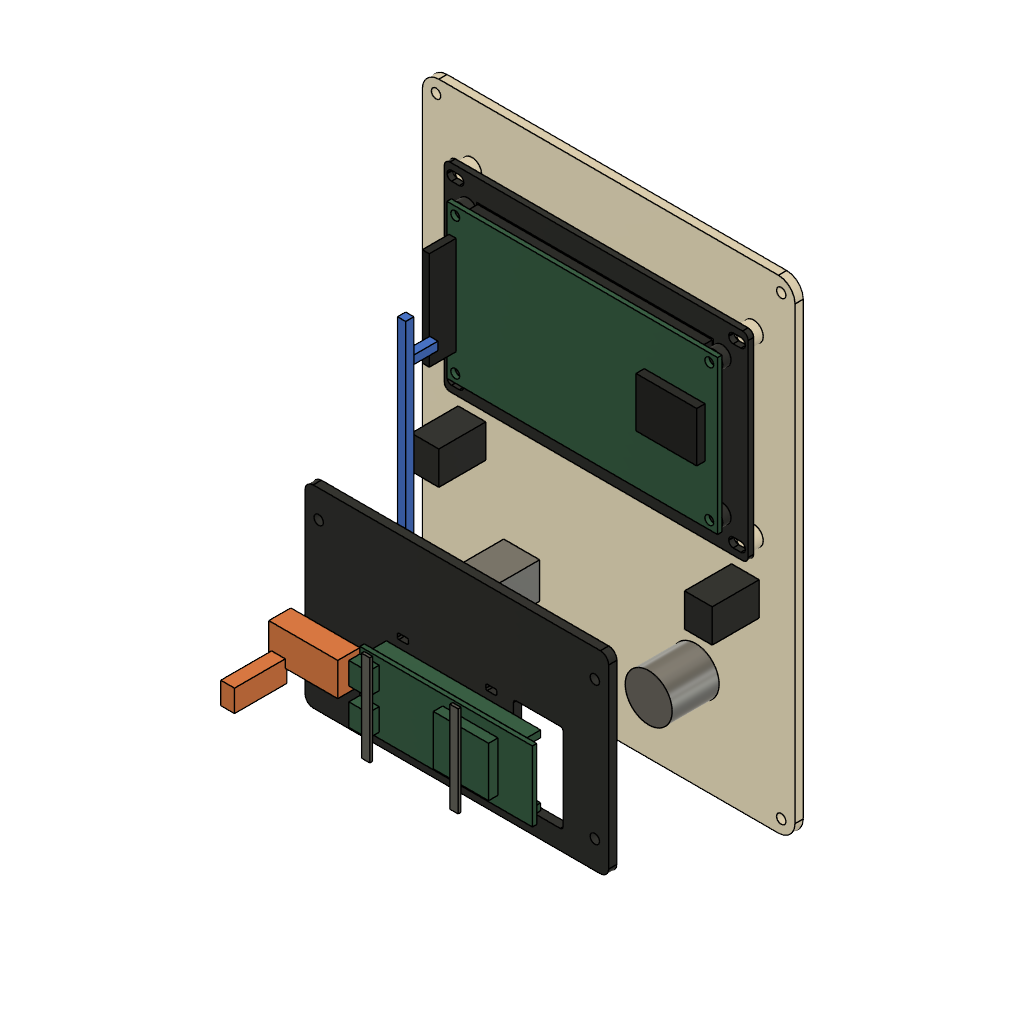
ORBIT-RevF-inspection (Autodesk Fusion 360 design; units mm, degrees)
part number: 2026-11-20-19-17-01-142
part number: 2026-11-20-19-17-03-286
part number: 2026-11-20-19-17-04-013
part number: 2026-11-20-19-17-06-329
part number: 2026-11-20-19-17-11-333
part number: 2026-11-20-19-17-15-780
part number: 2026-11-20-19-17-29-310
part number: 2026-11-20-19-17-54-071
part number: 2026-11-20-19-17-56-815
part number: 2026-11-20-19-17-57-486
part number: 2026-11-20-19-17-58-164
part number: 2026-11-20-19-17-59-377
part number: 2026-11-20-19-18-00-044
part number: 2026-11-20-19-18-00-747
part number: 2026-11-20-19-18-02-604
part number: 2026-11-20-19-18-04-519
part number: 2026-11-20-19-18-05-237
part number: 2026-11-20-19-20-05-078
part number: 2026-11-20-19-20-08-985
part number: 2026-11-20-19-20-10-407
part number: 2026-11-20-19-20-11-880
Autodesk Fusion 360 part; units mm, degrees
(part 1 of 2)
ref_plane "WorkPlane1" through (0, 0, 0) normal (0, 0, 1) x (1, 0, 0) in component "01 Ivory front panel"
sketch "Front panel" plane through (0, 0, 0) normal (0, 0, 1) x (1, 0, 0) in component "01 Ivory front panel"
  line L0 (6, 0) -> (129, 0)
  arc A0 (129, 0) -> (135, 6) centre (129, 6) ccw
  line L1 (135, 6) -> (135, 169)
  arc A1 (135, 169) -> (129, 175) centre (129, 169) ccw
  line L2 (129, 175) -> (6, 175)
  arc A2 (6, 175) -> (0, 169) centre (6, 169) ccw
  line L3 (0, 169) -> (0, 6)
  arc A3 (0, 6) -> (6, 0) centre (6, 6) ccw
extrude "Front panel (1)" add sketch "Front panel" along normal blind 3 makes body 1 in component "01 Ivory front panel"
ref_plane "WorkPlane2" through (0, 0, 0) normal (0, 0, 1) x (1, 0, 0) in component "01 Ivory front panel"
sketch "480x320 landscape aperture" plane through (0, 0, 0) normal (0, 0, 1) x (1, 0, 0) in component "01 Ivory front panel"
  line L0 (30.6, 96.1) -> (104.4, 96.1)
  arc A0 (104.4, 96.1) -> (104.6, 96.3) centre (104.4, 96.3) ccw
  line L1 (104.6, 96.3) -> (104.6, 145.7)
  arc A1 (104.6, 145.7) -> (104.4, 145.9) centre (104.4, 145.7) ccw
  line L2 (104.4, 145.9) -> (30.6, 145.9)
  arc A2 (30.6, 145.9) -> (30.4, 145.7) centre (30.6, 145.7) ccw
  line L3 (30.4, 145.7) -> (30.4, 96.3)
  arc A3 (30.4, 96.3) -> (30.6, 96.1) centre (30.6, 96.3) ccw
extrude "480x320 landscape aperture (1)" cut sketch "480x320 landscape aperture" along normal blind 3 bodies 1 in component "01 Ivory front panel"
ref_plane "WorkPlane3" through (0, 0, 0) normal (0, 0, 1) x (1, 0, 0) in component "01 Ivory front panel"
sketch "Select push encoder" plane through (0, 0, 0) normal (0, 0, 1) x (1, 0, 0) in component "01 Ivory front panel"
  circle A0 centre (36, 36) radius 3.7
extrude "Select push encoder (1)" cut sketch "Select push encoder" along normal blind 3 bodies 1 in component "01 Ivory front panel"
ref_plane "WorkPlane4" through (0, 0, 0) normal (0, 0, 1) x (1, 0, 0) in component "01 Ivory front panel"
sketch "Intensity pot" plane through (0, 0, 0) normal (0, 0, 1) x (1, 0, 0) in component "01 Ivory front panel"
  circle A0 centre (99, 36) radius 3.7
extrude "Intensity pot (1)" cut sketch "Intensity pot" along normal blind 3 bodies 1 in component "01 Ivory front panel"
ref_plane "WorkPlane5" through (0, 0, 0) normal (0, 0, 1) x (1, 0, 0) in component "01 Ivory front panel"
sketch "HOLD" plane through (0, 0, 0) normal (0, 0, 1) x (1, 0, 0) in component "01 Ivory front panel"
  circle A0 centre (18, 70) radius 3.2
extrude "HOLD (1)" cut sketch "HOLD" along normal blind 3 bodies 1 in component "01 Ivory front panel"
ref_plane "WorkPlane6" through (0, 0, 0) normal (0, 0, 1) x (1, 0, 0) in component "01 Ivory front panel"
sketch "GRID" plane through (0, 0, 0) normal (0, 0, 1) x (1, 0, 0) in component "01 Ivory front panel"
  circle A0 centre (117, 70) radius 3.2
extrude "GRID (1)" cut sketch "GRID" along normal blind 3 bodies 1 in component "01 Ivory front panel"
ref_plane "WorkPlane7" through (0, 0, 0) normal (0, 0, 1) x (1, 0, 0) in component "01 Ivory front panel"
sketch "Decorative disk slot" plane through (0, 0, 0) normal (0, 0, 1) x (1, 0, 0) in component "01 Ivory front panel"
  line L0 (51.5, 16) -> (83.5, 16)
  arc A0 (83.5, 16) -> (84.5, 17) centre (83.5, 17) ccw
  line L1 (84.5, 17) -> (84.5, 17.4)
  arc A1 (84.5, 17.4) -> (83.5, 18.4) centre (83.5, 17.4) ccw
  line L2 (83.5, 18.4) -> (51.5, 18.4)
  arc A2 (51.5, 18.4) -> (50.5, 17.4) centre (51.5, 17.4) ccw
  line L3 (50.5, 17.4) -> (50.5, 17)
  arc A3 (50.5, 17) -> (51.5, 16) centre (51.5, 17) ccw
extrude "Decorative disk slot (1)" cut sketch "Decorative disk slot" along normal blind 0.8 bodies 1 in component "01 Ivory front panel"
ref_plane "WorkPlane8" through (0, 0, 0) normal (0, 0, 1) x (1, 0, 0) in component "01 Ivory front panel"
sketch "M3 panel fixing" plane through (0, 0, 0) normal (0, 0, 1) x (1, 0, 0) in component "01 Ivory front panel"
  circle A0 centre (5, 5) radius 1.7
extrude "M3 panel fixing (1)" cut sketch "M3 panel fixing" along normal blind 3 bodies 1 in component "01 Ivory front panel"
ref_plane "WorkPlane9" through (0, 0, 0) normal (0, 0, 1) x (1, 0, 0) in component "01 Ivory front panel"
sketch "M3 panel fixing (1)" plane through (0, 0, 0) normal (0, 0, 1) x (1, 0, 0) in component "01 Ivory front panel"
  circle A0 centre (130, 5) radius 1.7
extrude "M3 panel fixing (2)" cut sketch "M3 panel fixing (1)" along normal blind 3 bodies 1 in component "01 Ivory front panel"
ref_plane "WorkPlane10" through (0, 0, 0) normal (0, 0, 1) x (1, 0, 0) in component "01 Ivory front panel"
sketch "M3 panel fixing (2)" plane through (0, 0, 0) normal (0, 0, 1) x (1, 0, 0) in component "01 Ivory front panel"
  circle A0 centre (5, 170) radius 1.7
extrude "M3 panel fixing (3)" cut sketch "M3 panel fixing (2)" along normal blind 3 bodies 1 in component "01 Ivory front panel"
ref_plane "WorkPlane11" through (0, 0, 0) normal (0, 0, 1) x (1, 0, 0) in component "01 Ivory front panel"
sketch "M3 panel fixing (3)" plane through (0, 0, 0) normal (0, 0, 1) x (1, 0, 0) in component "01 Ivory front panel"
  circle A0 centre (130, 170) radius 1.7
extrude "M3 panel fixing (4)" cut sketch "M3 panel fixing (3)" along normal blind 3 bodies 1 in component "01 Ivory front panel"
ref_plane "WorkPlane1" through (0, 0, 3) normal (0, 0, 1) x (1, 0, 0) in component "02 Ivory shell"
sketch "Shell exterior" plane through (0, 0, 3) normal (0, 0, 1) x (1, 0, 0) in component "02 Ivory shell"
  line L0 (6, 0) -> (129, 0)
  arc A0 (129, 0) -> (135, 6) centre (129, 6) ccw
  line L1 (135, 6) -> (135, 169)
  arc A1 (135, 169) -> (129, 175) centre (129, 169) ccw
  line L2 (129, 175) -> (6, 175)
  arc A2 (6, 175) -> (0, 169) centre (6, 169) ccw
  line L3 (0, 169) -> (0, 6)
  arc A3 (0, 6) -> (6, 0) centre (6, 6) ccw
extrude "Shell exterior (1)" add sketch "Shell exterior" along normal blind 89 separate body makes body 2 in component "02 Ivory shell"
ref_plane "WorkPlane2" through (0, 0, 3) normal (0, 0, 1) x (1, 0, 0) in component "02 Ivory shell"
sketch "Open cavity" plane through (0, 0, 3) normal (0, 0, 1) x (1, 0, 0) in component "02 Ivory shell"
  line L0 (6, 2.4) -> (129, 2.4)
  arc A0 (129, 2.4) -> (132.6, 6) centre (129, 6) ccw
  line L1 (132.6, 6) -> (132.6, 169)
  arc A1 (132.6, 169) -> (129, 172.6) centre (129, 169) ccw
  line L2 (129, 172.6) -> (6, 172.6)
  arc A2 (6, 172.6) -> (2.4, 169) centre (6, 169) ccw
  line L3 (2.4, 169) -> (2.4, 6)
  arc A3 (2.4, 6) -> (6, 2.4) centre (6, 6) ccw
extrude "Open cavity (1)" cut sketch "Open cavity" along normal blind 89 bodies 2 in component "02 Ivory shell"
ref_plane "WorkPlane3" through (0, 0, 3) normal (0, 0, 1) x (1, 0, 0) in component "02 Ivory shell"
sketch "M3 corner boss" plane through (0, 0, 3) normal (0, 0, 1) x (1, 0, 0) in component "02 Ivory shell"
  circle A0 centre (5, 5) radius 4
extrude "M3 corner boss (1)" add sketch "M3 corner boss" along normal blind 8 bodies 2 in component "02 Ivory shell"
ref_plane "WorkPlane4" through (0, 0, 3) normal (0, 0, 1) x (1, 0, 0) in component "02 Ivory shell"
sketch "M3 through bore" plane through (0, 0, 3) normal (0, 0, 1) x (1, 0, 0) in component "02 Ivory shell"
  circle A0 centre (5, 5) radius 1.7
extrude "M3 through bore (1)" cut sketch "M3 through bore" along normal blind 8 bodies 2 in component "02 Ivory shell"
ref_plane "WorkPlane5" through (0, 0, 84) normal (0, 0, 1) x (1, 0, 0) in component "02 Ivory shell"
sketch "M3 corner boss (1)" plane through (0, 0, 84) normal (0, 0, 1) x (1, 0, 0) in component "02 Ivory shell"
  circle A0 centre (5, 5) radius 4
extrude "M3 corner boss (2)" add sketch "M3 corner boss (1)" along normal blind 8 bodies 2 in component "02 Ivory shell"
ref_plane "WorkPlane6" through (0, 0, 84) normal (0, 0, 1) x (1, 0, 0) in component "02 Ivory shell"
sketch "M3 through bore (1)" plane through (0, 0, 84) normal (0, 0, 1) x (1, 0, 0) in component "02 Ivory shell"
  circle A0 centre (5, 5) radius 1.7
extrude "M3 through bore (2)" cut sketch "M3 through bore (1)" along normal blind 8 bodies 2 in component "02 Ivory shell"
ref_plane "WorkPlane7" through (0, 0, 3) normal (0, 0, 1) x (1, 0, 0) in component "02 Ivory shell"
sketch "M3 corner boss (2)" plane through (0, 0, 3) normal (0, 0, 1) x (1, 0, 0) in component "02 Ivory shell"
  circle A0 centre (130, 5) radius 4
extrude "M3 corner boss (3)" add sketch "M3 corner boss (2)" along normal blind 8 bodies 2 in component "02 Ivory shell"
ref_plane "WorkPlane8" through (0, 0, 3) normal (0, 0, 1) x (1, 0, 0) in component "02 Ivory shell"
sketch "M3 through bore (2)" plane through (0, 0, 3) normal (0, 0, 1) x (1, 0, 0) in component "02 Ivory shell"
  circle A0 centre (130, 5) radius 1.7
extrude "M3 through bore (3)" cut sketch "M3 through bore (2)" along normal blind 8 bodies 2 in component "02 Ivory shell"
ref_plane "WorkPlane9" through (0, 0, 84) normal (0, 0, 1) x (1, 0, 0) in component "02 Ivory shell"
sketch "M3 corner boss (3)" plane through (0, 0, 84) normal (0, 0, 1) x (1, 0, 0) in component "02 Ivory shell"
  circle A0 centre (130, 5) radius 4
extrude "M3 corner boss (4)" add sketch "M3 corner boss (3)" along normal blind 8 bodies 2 in component "02 Ivory shell"
ref_plane "WorkPlane10" through (0, 0, 84) normal (0, 0, 1) x (1, 0, 0) in component "02 Ivory shell"
sketch "M3 through bore (3)" plane through (0, 0, 84) normal (0, 0, 1) x (1, 0, 0) in component "02 Ivory shell"
  circle A0 centre (130, 5) radius 1.7
extrude "M3 through bore (4)" cut sketch "M3 through bore (3)" along normal blind 8 bodies 2 in component "02 Ivory shell"
ref_plane "WorkPlane11" through (0, 0, 3) normal (0, 0, 1) x (1, 0, 0) in component "02 Ivory shell"
sketch "M3 corner boss (4)" plane through (0, 0, 3) normal (0, 0, 1) x (1, 0, 0) in component "02 Ivory shell"
  circle A0 centre (5, 170) radius 4
extrude "M3 corner boss (5)" add sketch "M3 corner boss (4)" along normal blind 8 bodies 2 in component "02 Ivory shell"
ref_plane "WorkPlane12" through (0, 0, 3) normal (0, 0, 1) x (1, 0, 0) in component "02 Ivory shell"
sketch "M3 through bore (4)" plane through (0, 0, 3) normal (0, 0, 1) x (1, 0, 0) in component "02 Ivory shell"
  circle A0 centre (5, 170) radius 1.7
extrude "M3 through bore (5)" cut sketch "M3 through bore (4)" along normal blind 8 bodies 2 in component "02 Ivory shell"
ref_plane "WorkPlane13" through (0, 0, 84) normal (0, 0, 1) x (1, 0, 0) in component "02 Ivory shell"
sketch "M3 corner boss (5)" plane through (0, 0, 84) normal (0, 0, 1) x (1, 0, 0) in component "02 Ivory shell"
  circle A0 centre (5, 170) radius 4
extrude "M3 corner boss (6)" add sketch "M3 corner boss (5)" along normal blind 8 bodies 2 in component "02 Ivory shell"
ref_plane "WorkPlane14" through (0, 0, 84) normal (0, 0, 1) x (1, 0, 0) in component "02 Ivory shell"
sketch "M3 through bore (5)" plane through (0, 0, 84) normal (0, 0, 1) x (1, 0, 0) in component "02 Ivory shell"
  circle A0 centre (5, 170) radius 1.7
extrude "M3 through bore (6)" cut sketch "M3 through bore (5)" along normal blind 8 bodies 2 in component "02 Ivory shell"
ref_plane "WorkPlane15" through (0, 0, 3) normal (0, 0, 1) x (1, 0, 0) in component "02 Ivory shell"
sketch "M3 corner boss (6)" plane through (0, 0, 3) normal (0, 0, 1) x (1, 0, 0) in component "02 Ivory shell"
  circle A0 centre (130, 170) radius 4
extrude "M3 corner boss (7)" add sketch "M3 corner boss (6)" along normal blind 8 bodies 2 in component "02 Ivory shell"
ref_plane "WorkPlane16" through (0, 0, 3) normal (0, 0, 1) x (1, 0, 0) in component "02 Ivory shell"
sketch "M3 through bore (6)" plane through (0, 0, 3) normal (0, 0, 1) x (1, 0, 0) in component "02 Ivory shell"
  circle A0 centre (130, 170) radius 1.7
extrude "M3 through bore (7)" cut sketch "M3 through bore (6)" along normal blind 8 bodies 2 in component "02 Ivory shell"
ref_plane "WorkPlane17" through (0, 0, 84) normal (0, 0, 1) x (1, 0, 0) in component "02 Ivory shell"
sketch "M3 corner boss (7)" plane through (0, 0, 84) normal (0, 0, 1) x (1, 0, 0) in component "02 Ivory shell"
  circle A0 centre (130, 170) radius 4
extrude "M3 corner boss (8)" add sketch "M3 corner boss (7)" along normal blind 8 bodies 2 in component "02 Ivory shell"
ref_plane "WorkPlane18" through (0, 0, 84) normal (0, 0, 1) x (1, 0, 0) in component "02 Ivory shell"
sketch "M3 through bore (7)" plane through (0, 0, 84) normal (0, 0, 1) x (1, 0, 0) in component "02 Ivory shell"
  circle A0 centre (130, 170) radius 1.7
extrude "M3 through bore (8)" cut sketch "M3 through bore (7)" along normal blind 8 bodies 2 in component "02 Ivory shell"
ref_plane "WorkPlane1" through (0, 0, 92) normal (0, 0, 1) x (1, 0, 0) in component "03 Ivory USB rear cover"
sketch "Rear cover" plane through (0, 0, 92) normal (0, 0, 1) x (1, 0, 0) in component "03 Ivory USB rear cover"
  line L0 (6, 0) -> (129, 0)
  arc A0 (129, 0) -> (135, 6) centre (129, 6) ccw
  line L1 (135, 6) -> (135, 169)
  arc A1 (135, 169) -> (129, 175) centre (129, 169) ccw
  line L2 (129, 175) -> (6, 175)
  arc A2 (6, 175) -> (0, 169) centre (6, 169) ccw
  line L3 (0, 169) -> (0, 6)
  arc A3 (0, 6) -> (6, 0) centre (6, 6) ccw
extrude "Rear cover (1)" add sketch "Rear cover" along normal blind 3 separate body makes body 3 in component "03 Ivory USB rear cover"
ref_plane "WorkPlane2" through (0, 0, 92) normal (0, 0, 1) x (1, 0, 0) in component "03 Ivory USB rear cover"
sketch "Rear screw" plane through (0, 0, 92) normal (0, 0, 1) x (1, 0, 0) in component "03 Ivory USB rear cover"
  circle A0 centre (5, 5) radius 1.7
extrude "Rear screw (1)" cut sketch "Rear screw" along normal blind 3 bodies 3 in component "03 Ivory USB rear cover"
ref_plane "WorkPlane3" through (0, 0, 92) normal (0, 0, 1) x (1, 0, 0) in component "03 Ivory USB rear cover"
sketch "Rear screw (1)" plane through (0, 0, 92) normal (0, 0, 1) x (1, 0, 0) in component "03 Ivory USB rear cover"
  circle A0 centre (130, 5) radius 1.7
extrude "Rear screw (2)" cut sketch "Rear screw (1)" along normal blind 3 bodies 3 in component "03 Ivory USB rear cover"
ref_plane "WorkPlane4" through (0, 0, 92) normal (0, 0, 1) x (1, 0, 0) in component "03 Ivory USB rear cover"
sketch "Rear screw (2)" plane through (0, 0, 92) normal (0, 0, 1) x (1, 0, 0) in component "03 Ivory USB rear cover"
  circle A0 centre (5, 170) radius 1.7
extrude "Rear screw (3)" cut sketch "Rear screw (2)" along normal blind 3 bodies 3 in component "03 Ivory USB rear cover"
ref_plane "WorkPlane5" through (0, 0, 92) normal (0, 0, 1) x (1, 0, 0) in component "03 Ivory USB rear cover"
sketch "Rear screw (3)" plane through (0, 0, 92) normal (0, 0, 1) x (1, 0, 0) in component "03 Ivory USB rear cover"
  circle A0 centre (130, 170) radius 1.7
extrude "Rear screw (4)" cut sketch "Rear screw (3)" along normal blind 3 bodies 3 in component "03 Ivory USB rear cover"
ref_plane "WorkPlane6" through (0, 0, 92) normal (0, 0, 1) x (1, 0, 0) in component "03 Ivory USB rear cover"
sketch "USB-C plug pass-through - deburr edges" plane through (0, 0, 92) normal (0, 0, 1) x (1, 0, 0) in component "03 Ivory USB rear cover"
  line L0 (17, 24) -> (29, 24)
  arc A0 (29, 24) -> (31, 26) centre (29, 26) ccw
  line L1 (31, 26) -> (31, 32)
  arc A1 (31, 32) -> (29, 34) centre (29, 32) ccw
  line L2 (29, 34) -> (17, 34)
  arc A2 (17, 34) -> (15, 32) centre (17, 32) ccw
  line L3 (15, 32) -> (15, 26)
  arc A3 (15, 26) -> (17, 24) centre (17, 26) ccw
extrude "USB-C plug pass-through - deburr edges (1)" cut sketch "USB-C plug pass-through - deburr edges" along normal blind 3 bodies 3 in component "03 Ivory USB rear cover"
ref_plane "WorkPlane7" through (0, 0, 92) normal (0, 0, 1) x (1, 0, 0) in component "03 Ivory USB rear cover"
sketch "Rear vent" plane through (0, 0, 92) normal (0, 0, 1) x (1, 0, 0) in component "03 Ivory USB rear cover"
  line L0 (36, 145) -> (37, 145)
  arc A0 (37, 145) -> (38, 146) centre (37, 146) ccw
  line L1 (38, 146) -> (38, 159)
  arc A1 (38, 159) -> (37, 160) centre (37, 159) ccw
  line L2 (37, 160) -> (36, 160)
  arc A2 (36, 160) -> (35, 159) centre (36, 159) ccw
  line L3 (35, 159) -> (35, 146)
  arc A3 (35, 146) -> (36, 145) centre (36, 146) ccw
extrude "Rear vent (1)" cut sketch "Rear vent" along normal blind 3 bodies 3 in component "03 Ivory USB rear cover"
ref_plane "WorkPlane8" through (0, 0, 92) normal (0, 0, 1) x (1, 0, 0) in component "03 Ivory USB rear cover"
sketch "Rear vent (1)" plane through (0, 0, 92) normal (0, 0, 1) x (1, 0, 0) in component "03 Ivory USB rear cover"
  line L0 (46, 145) -> (47, 145)
  arc A0 (47, 145) -> (48, 146) centre (47, 146) ccw
  line L1 (48, 146) -> (48, 159)
  arc A1 (48, 159) -> (47, 160) centre (47, 159) ccw
  line L2 (47, 160) -> (46, 160)
  arc A2 (46, 160) -> (45, 159) centre (46, 159) ccw
  line L3 (45, 159) -> (45, 146)
  arc A3 (45, 146) -> (46, 145) centre (46, 146) ccw
extrude "Rear vent (2)" cut sketch "Rear vent (1)" along normal blind 3 bodies 3 in component "03 Ivory USB rear cover"
ref_plane "WorkPlane9" through (0, 0, 92) normal (0, 0, 1) x (1, 0, 0) in component "03 Ivory USB rear cover"
sketch "Rear vent (2)" plane through (0, 0, 92) normal (0, 0, 1) x (1, 0, 0) in component "03 Ivory USB rear cover"
  line L0 (56, 145) -> (57, 145)
  arc A0 (57, 145) -> (58, 146) centre (57, 146) ccw
  line L1 (58, 146) -> (58, 159)
  arc A1 (58, 159) -> (57, 160) centre (57, 159) ccw
  line L2 (57, 160) -> (56, 160)
  arc A2 (56, 160) -> (55, 159) centre (56, 159) ccw
  line L3 (55, 159) -> (55, 146)
  arc A3 (55, 146) -> (56, 145) centre (56, 146) ccw
extrude "Rear vent (3)" cut sketch "Rear vent (2)" along normal blind 3 bodies 3 in component "03 Ivory USB rear cover"
ref_plane "WorkPlane10" through (0, 0, 92) normal (0, 0, 1) x (1, 0, 0) in component "03 Ivory USB rear cover"
sketch "Rear vent (3)" plane through (0, 0, 92) normal (0, 0, 1) x (1, 0, 0) in component "03 Ivory USB rear cover"
  line L0 (66, 145) -> (67, 145)
  arc A0 (67, 145) -> (68, 146) centre (67, 146) ccw
  line L1 (68, 146) -> (68, 159)
  arc A1 (68, 159) -> (67, 160) centre (67, 159) ccw
  line L2 (67, 160) -> (66, 160)
  arc A2 (66, 160) -> (65, 159) centre (66, 159) ccw
  line L3 (65, 159) -> (65, 146)
  arc A3 (65, 146) -> (66, 145) centre (66, 146) ccw
extrude "Rear vent (4)" cut sketch "Rear vent (3)" along normal blind 3 bodies 3 in component "03 Ivory USB rear cover"
ref_plane "WorkPlane11" through (0, 0, 92) normal (0, 0, 1) x (1, 0, 0) in component "03 Ivory USB rear cover"
sketch "Rear vent (4)" plane through (0, 0, 92) normal (0, 0, 1) x (1, 0, 0) in component "03 Ivory USB rear cover"
  line L0 (76, 145) -> (77, 145)
  arc A0 (77, 145) -> (78, 146) centre (77, 146) ccw
  line L1 (78, 146) -> (78, 159)
  arc A1 (78, 159) -> (77, 160) centre (77, 159) ccw
  line L2 (77, 160) -> (76, 160)
  arc A2 (76, 160) -> (75, 159) centre (76, 159) ccw
  line L3 (75, 159) -> (75, 146)
  arc A3 (75, 146) -> (76, 145) centre (76, 146) ccw
extrude "Rear vent (5)" cut sketch "Rear vent (4)" along normal blind 3 bodies 3 in component "03 Ivory USB rear cover"
ref_plane "WorkPlane12" through (0, 0, 92) normal (0, 0, 1) x (1, 0, 0) in component "03 Ivory USB rear cover"
sketch "Rear vent (5)" plane through (0, 0, 92) normal (0, 0, 1) x (1, 0, 0) in component "03 Ivory USB rear cover"
  line L0 (86, 145) -> (87, 145)
  arc A0 (87, 145) -> (88, 146) centre (87, 146) ccw
  line L1 (88, 146) -> (88, 159)
  arc A1 (88, 159) -> (87, 160) centre (87, 159) ccw
  line L2 (87, 160) -> (86, 160)
  arc A2 (86, 160) -> (85, 159) centre (86, 159) ccw
  line L3 (85, 159) -> (85, 146)
  arc A3 (85, 146) -> (86, 145) centre (86, 146) ccw
extrude "Rear vent (6)" cut sketch "Rear vent (5)" along normal blind 3 bodies 3 in component "03 Ivory USB rear cover"
ref_plane "WorkPlane13" through (0, 0, 92) normal (0, 0, 1) x (1, 0, 0) in component "03 Ivory USB rear cover"
sketch "Rear vent (6)" plane through (0, 0, 92) normal (0, 0, 1) x (1, 0, 0) in component "03 Ivory USB rear cover"
  line L0 (96, 145) -> (97, 145)
  arc A0 (97, 145) -> (98, 146) centre (97, 146) ccw
  line L1 (98, 146) -> (98, 159)
  arc A1 (98, 159) -> (97, 160) centre (97, 159) ccw
  line L2 (97, 160) -> (96, 160)
  arc A2 (96, 160) -> (95, 159) centre (96, 159) ccw
  line L3 (95, 159) -> (95, 146)
  arc A3 (95, 146) -> (96, 145) centre (96, 146) ccw
extrude "Rear vent (7)" cut sketch "Rear vent (6)" along normal blind 3 bodies 3 in component "03 Ivory USB rear cover"
ref_plane "WorkPlane14" through (0, 0, 92) normal (0, 0, 1) x (1, 0, 0) in component "03 Ivory USB rear cover"
sketch "Rear vent (7)" plane through (0, 0, 92) normal (0, 0, 1) x (1, 0, 0) in component "03 Ivory USB rear cover"
  line L0 (106, 145) -> (107, 145)
  arc A0 (107, 145) -> (108, 146) centre (107, 146) ccw
  line L1 (108, 146) -> (108, 159)
  arc A1 (108, 159) -> (107, 160) centre (107, 159) ccw
  line L2 (107, 160) -> (106, 160)
  arc A2 (106, 160) -> (105, 159) centre (106, 159) ccw
  line L3 (105, 159) -> (105, 146)
  arc A3 (105, 146) -> (106, 145) centre (106, 146) ccw
extrude "Rear vent (8)" cut sketch "Rear vent (7)" along normal blind 3 bodies 3 in component "03 Ivory USB rear cover"
ref_plane "WorkPlane15" through (0, 0, 92) normal (0, 0, 1) x (1, 0, 0) in component "03 Ivory USB rear cover"
sketch "Rear cable tie anchor" plane through (0, 0, 92) normal (0, 0, 1) x (1, 0, 0) in component "03 Ivory USB rear cover"
  line L0 (20.5, 20) -> (25.5, 20)
  arc A0 (25.5, 20) -> (26, 20.5) centre (25.5, 20.5) ccw
  line L1 (26, 20.5) -> (26, 21.5)
  arc A1 (26, 21.5) -> (25.5, 22) centre (25.5, 21.5) ccw
  line L2 (25.5, 22) -> (20.5, 22)
  arc A2 (20.5, 22) -> (20, 21.5) centre (20.5, 21.5) ccw
  line L3 (20, 21.5) -> (20, 20.5)
  arc A3 (20, 20.5) -> (20.5, 20) centre (20.5, 20.5) ccw
extrude "Rear cable tie anchor (1)" cut sketch "Rear cable tie anchor" along normal blind 3 bodies 3 in component "03 Ivory USB rear cover"
ref_plane "WorkPlane16" through (0, 0, 92) normal (0, 0, 1) x (1, 0, 0) in component "03 Ivory USB rear cover"
sketch "Rear cable tie anchor (1)" plane through (0, 0, 92) normal (0, 0, 1) x (1, 0, 0) in component "03 Ivory USB rear cover"
  line L0 (20.5, 36) -> (25.5, 36)
  arc A0 (25.5, 36) -> (26, 36.5) centre (25.5, 36.5) ccw
  line L1 (26, 36.5) -> (26, 37.5)
  arc A1 (26, 37.5) -> (25.5, 38) centre (25.5, 37.5) ccw
  line L2 (25.5, 38) -> (20.5, 38)
  arc A2 (20.5, 38) -> (20, 37.5) centre (20.5, 37.5) ccw
  line L3 (20, 37.5) -> (20, 36.5)
  arc A3 (20, 36.5) -> (20.5, 36) centre (20.5, 36.5) ccw
extrude "Rear cable tie anchor (2)" cut sketch "Rear cable tie anchor (1)" along normal blind 3 bodies 3 in component "03 Ivory USB rear cover"
ref_plane "WorkPlane1" through (0, 0, -2) normal (0, 0, 1) x (1, 0, 0) in component "04 Charcoal landscape bezel"
sketch "Landscape bezel" plane through (0, 0, -2) normal (0, 0, 1) x (1, 0, 0) in component "04 Charcoal landscape bezel"
  line L0 (29.4, 92.1) -> (105.6, 92.1)
  arc A0 (105.6, 92.1) -> (108.6, 95.1) centre (105.6, 95.1) ccw
  line L1 (108.6, 95.1) -> (108.6, 146.9)
  arc A1 (108.6, 146.9) -> (105.6, 149.9) centre (105.6, 146.9) ccw
  line L2 (105.6, 149.9) -> (29.4, 149.9)
  arc A2 (29.4, 149.9) -> (26.4, 146.9) centre (29.4, 146.9) ccw
  line L3 (26.4, 146.9) -> (26.4, 95.1)
  arc A3 (26.4, 95.1) -> (29.4, 92.1) centre (29.4, 95.1) ccw
extrude "Landscape bezel (1)" add sketch "Landscape bezel" along normal blind 2 separate body makes body 4 in component "04 Charcoal landscape bezel"
ref_plane "WorkPlane2" through (0, 0, -2) normal (0, 0, 1) x (1, 0, 0) in component "04 Charcoal landscape bezel"
sketch "Aperture" plane through (0, 0, -2) normal (0, 0, 1) x (1, 0, 0) in component "04 Charcoal landscape bezel"
  line L0 (30.6, 96.1) -> (104.4, 96.1)
  arc A0 (104.4, 96.1) -> (104.6, 96.3) centre (104.4, 96.3) ccw
  line L1 (104.6, 96.3) -> (104.6, 145.7)
  arc A1 (104.6, 145.7) -> (104.4, 145.9) centre (104.4, 145.7) ccw
  line L2 (104.4, 145.9) -> (30.6, 145.9)
  arc A2 (30.6, 145.9) -> (30.4, 145.7) centre (30.6, 145.7) ccw
  line L3 (30.4, 145.7) -> (30.4, 96.3)
  arc A3 (30.4, 96.3) -> (30.6, 96.1) centre (30.6, 96.3) ccw
extrude "Aperture (1)" cut sketch "Aperture" along normal blind 2 bodies 4 in component "04 Charcoal landscape bezel"
ref_plane "WorkPlane12" through (0, 0, 0) normal (0, 0, 1) x (1, 0, 0) in component "01 Ivory front panel"
sketch "Bezel socket" plane through (0, 0, 0) normal (0, 0, 1) x (1, 0, 0) in component "01 Ivory front panel"
  circle A0 centre (28.4, 94.1) radius 1.1
extrude "Bezel socket (1)" cut sketch "Bezel socket" along normal blind 2.2 bodies 1 in component "01 Ivory front panel"
ref_plane "WorkPlane3" through (0, 0, 0) normal (0, 0, 1) x (1, 0, 0) in component "04 Charcoal landscape bezel"
sketch "Bezel peg" plane through (0, 0, 0) normal (0, 0, 1) x (1, 0, 0) in component "04 Charcoal landscape bezel"
  circle A0 centre (28.4, 94.1) radius 0.9
extrude "Bezel peg (1)" add sketch "Bezel peg" along normal blind 2 bodies 4 in component "04 Charcoal landscape bezel"
ref_plane "WorkPlane13" through (0, 0, 0) normal (0, 0, 1) x (1, 0, 0) in component "01 Ivory front panel"
sketch "Bezel socket (1)" plane through (0, 0, 0) normal (0, 0, 1) x (1, 0, 0) in component "01 Ivory front panel"
  circle A0 centre (106.6, 147.9) radius 1.1
extrude "Bezel socket (2)" cut sketch "Bezel socket (1)" along normal blind 2.2 bodies 1 in component "01 Ivory front panel"
ref_plane "WorkPlane4" through (0, 0, 0) normal (0, 0, 1) x (1, 0, 0) in component "04 Charcoal landscape bezel"
sketch "Bezel peg (1)" plane through (0, 0, 0) normal (0, 0, 1) x (1, 0, 0) in component "04 Charcoal landscape bezel"
  circle A0 centre (106.6, 147.9) radius 0.9
extrude "Bezel peg (2)" add sketch "Bezel peg (1)" along normal blind 2 bodies 4 in component "04 Charcoal landscape bezel"
ref_plane "WorkPlane14" through (0, 0, 3) normal (0, 0, 1) x (1, 0, 0) in component "01 Ivory front panel"
sketch "Carrier support" plane through (0, 0, 3) normal (0, 0, 1) x (1, 0, 0) in component "01 Ivory front panel"
  circle A0 centre (18, 89) radius 3.5
extrude "Carrier support (1)" add sketch "Carrier support" along normal blind 4 bodies 1 in component "01 Ivory front panel"
ref_plane "WorkPlane15" through (0, 0, 2) normal (0, 0, 1) x (1, 0, 0) in component "01 Ivory front panel"
sketch "M3 insert pilot" plane through (0, 0, 2) normal (0, 0, 1) x (1, 0, 0) in component "01 Ivory front panel"
  circle A0 centre (18, 89) radius 2.2
extrude "M3 insert pilot (1)" cut sketch "M3 insert pilot" along normal blind 5 bodies 1 in component "01 Ivory front panel"
ref_plane "WorkPlane16" through (0, 0, 3) normal (0, 0, 1) x (1, 0, 0) in component "01 Ivory front panel"
sketch "Carrier support (1)" plane through (0, 0, 3) normal (0, 0, 1) x (1, 0, 0) in component "01 Ivory front panel"
  circle A0 centre (18, 153) radius 3.5
extrude "Carrier support (2)" add sketch "Carrier support (1)" along normal blind 4 bodies 1 in component "01 Ivory front panel"
ref_plane "WorkPlane17" through (0, 0, 2) normal (0, 0, 1) x (1, 0, 0) in component "01 Ivory front panel"
sketch "M3 insert pilot (1)" plane through (0, 0, 2) normal (0, 0, 1) x (1, 0, 0) in component "01 Ivory front panel"
  circle A0 centre (18, 153) radius 2.2
extrude "M3 insert pilot (2)" cut sketch "M3 insert pilot (1)" along normal blind 5 bodies 1 in component "01 Ivory front panel"
ref_plane "WorkPlane18" through (0, 0, 3) normal (0, 0, 1) x (1, 0, 0) in component "01 Ivory front panel"
sketch "Carrier support (2)" plane through (0, 0, 3) normal (0, 0, 1) x (1, 0, 0) in component "01 Ivory front panel"
  circle A0 centre (120, 89) radius 3.5
extrude "Carrier support (3)" add sketch "Carrier support (2)" along normal blind 4 bodies 1 in component "01 Ivory front panel"
ref_plane "WorkPlane19" through (0, 0, 2) normal (0, 0, 1) x (1, 0, 0) in component "01 Ivory front panel"
sketch "M3 insert pilot (2)" plane through (0, 0, 2) normal (0, 0, 1) x (1, 0, 0) in component "01 Ivory front panel"
  circle A0 centre (120, 89) radius 2.2
extrude "M3 insert pilot (3)" cut sketch "M3 insert pilot (2)" along normal blind 5 bodies 1 in component "01 Ivory front panel"
ref_plane "WorkPlane20" through (0, 0, 3) normal (0, 0, 1) x (1, 0, 0) in component "01 Ivory front panel"
sketch "Carrier support (3)" plane through (0, 0, 3) normal (0, 0, 1) x (1, 0, 0) in component "01 Ivory front panel"
  circle A0 centre (120, 153) radius 3.5
extrude "Carrier support (4)" add sketch "Carrier support (3)" along normal blind 4 bodies 1 in component "01 Ivory front panel"
ref_plane "WorkPlane21" through (0, 0, 2) normal (0, 0, 1) x (1, 0, 0) in component "01 Ivory front panel"
sketch "M3 insert pilot (3)" plane through (0, 0, 2) normal (0, 0, 1) x (1, 0, 0) in component "01 Ivory front panel"
  circle A0 centre (120, 153) radius 2.2
extrude "M3 insert pilot (4)" cut sketch "M3 insert pilot (3)" along normal blind 5 bodies 1 in component "01 Ivory front panel"
ref_plane "WorkPlane1" through (0, 0, 7) normal (0, 0, 1) x (1, 0, 0) in component "05 Replaceable MSP3525 display carrier"
sketch "Replaceable display carrier" plane through (0, 0, 7) normal (0, 0, 1) x (1, 0, 0) in component "05 Replaceable MSP3525 display carrier"
  line L0 (16, 85) -> (122, 85)
  arc A0 (122, 85) -> (124, 87) centre (122, 87) ccw
  line L1 (124, 87) -> (124, 155)
  arc A1 (124, 155) -> (122, 157) centre (122, 155) ccw
  line L2 (122, 157) -> (16, 157)
  arc A2 (16, 157) -> (14, 155) centre (16, 155) ccw
  line L3 (14, 155) -> (14, 87)
  arc A3 (14, 87) -> (16, 85) centre (16, 87) ccw
extrude "Replaceable display carrier (1)" add sketch "Replaceable display carrier" along normal blind 2 separate body makes body 5 in component "05 Replaceable MSP3525 display carrier"
ref_plane "WorkPlane2" through (0, 0, 7) normal (0, 0, 1) x (1, 0, 0) in component "05 Replaceable MSP3525 display carrier"
sketch "Glass and flex clearance" plane through (0, 0, 7) normal (0, 0, 1) x (1, 0, 0) in component "05 Replaceable MSP3525 display carrier"
  line L0 (25.7, 92.8) -> (111.4, 92.8)
  line L1 (111.4, 92.8) -> (111.4, 149.2)
  line L2 (111.4, 149.2) -> (25.7, 149.2)
  line L3 (25.7, 149.2) -> (25.7, 92.8)
extrude "Glass and flex clearance (1)" cut sketch "Glass and flex clearance" along normal blind 2 bodies 5 in component "05 Replaceable MSP3525 display carrier"
ref_plane "WorkPlane3" through (0, 0, 7) normal (0, 0, 1) x (1, 0, 0) in component "05 Replaceable MSP3525 display carrier"
sketch "Carrier lateral adjustment slot" plane through (0, 0, 7) normal (0, 0, 1) x (1, 0, 0) in component "05 Replaceable MSP3525 display carrier"
  line L0 (16.6, 87.3) -> (19.4, 87.3)
  arc A0 (19.4, 87.3) -> (21, 88.9) centre (19.4, 88.9) ccw
  line L1 (21, 88.9) -> (21, 89.1)
  arc A1 (21, 89.1) -> (19.4, 90.7) centre (19.4, 89.1) ccw
  line L2 (19.4, 90.7) -> (16.6, 90.7)
  arc A2 (16.6, 90.7) -> (15, 89.1) centre (16.6, 89.1) ccw
  line L3 (15, 89.1) -> (15, 88.9)
  arc A3 (15, 88.9) -> (16.6, 87.3) centre (16.6, 88.9) ccw
extrude "Carrier lateral adjustment slot (1)" cut sketch "Carrier lateral adjustment slot" along normal blind 2 bodies 5 in component "05 Replaceable MSP3525 display carrier"
ref_plane "WorkPlane4" through (0, 0, 7) normal (0, 0, 1) x (1, 0, 0) in component "05 Replaceable MSP3525 display carrier"
sketch "Carrier lateral adjustment slot (1)" plane through (0, 0, 7) normal (0, 0, 1) x (1, 0, 0) in component "05 Replaceable MSP3525 display carrier"
  line L0 (16.6, 151.3) -> (19.4, 151.3)
  arc A0 (19.4, 151.3) -> (21, 152.9) centre (19.4, 152.9) ccw
  line L1 (21, 152.9) -> (21, 153.1)
  arc A1 (21, 153.1) -> (19.4, 154.7) centre (19.4, 153.1) ccw
  line L2 (19.4, 154.7) -> (16.6, 154.7)
  arc A2 (16.6, 154.7) -> (15, 153.1) centre (16.6, 153.1) ccw
  line L3 (15, 153.1) -> (15, 152.9)
  arc A3 (15, 152.9) -> (16.6, 151.3) centre (16.6, 152.9) ccw
extrude "Carrier lateral adjustment slot (2)" cut sketch "Carrier lateral adjustment slot (1)" along normal blind 2 bodies 5 in component "05 Replaceable MSP3525 display carrier"
ref_plane "WorkPlane5" through (0, 0, 7) normal (0, 0, 1) x (1, 0, 0) in component "05 Replaceable MSP3525 display carrier"
sketch "Carrier lateral adjustment slot (2)" plane through (0, 0, 7) normal (0, 0, 1) x (1, 0, 0) in component "05 Replaceable MSP3525 display carrier"
  line L0 (118.6, 87.3) -> (121.4, 87.3)
  arc A0 (121.4, 87.3) -> (123, 88.9) centre (121.4, 88.9) ccw
  line L1 (123, 88.9) -> (123, 89.1)
  arc A1 (123, 89.1) -> (121.4, 90.7) centre (121.4, 89.1) ccw
  line L2 (121.4, 90.7) -> (118.6, 90.7)
  arc A2 (118.6, 90.7) -> (117, 89.1) centre (118.6, 89.1) ccw
  line L3 (117, 89.1) -> (117, 88.9)
  arc A3 (117, 88.9) -> (118.6, 87.3) centre (118.6, 88.9) ccw
extrude "Carrier lateral adjustment slot (3)" cut sketch "Carrier lateral adjustment slot (2)" along normal blind 2 bodies 5 in component "05 Replaceable MSP3525 display carrier"
ref_plane "WorkPlane6" through (0, 0, 7) normal (0, 0, 1) x (1, 0, 0) in component "05 Replaceable MSP3525 display carrier"
sketch "Carrier lateral adjustment slot (3)" plane through (0, 0, 7) normal (0, 0, 1) x (1, 0, 0) in component "05 Replaceable MSP3525 display carrier"
  line L0 (118.6, 151.3) -> (121.4, 151.3)
  arc A0 (121.4, 151.3) -> (123, 152.9) centre (121.4, 152.9) ccw
  line L1 (123, 152.9) -> (123, 153.1)
  arc A1 (123, 153.1) -> (121.4, 154.7) centre (121.4, 153.1) ccw
  line L2 (121.4, 154.7) -> (118.6, 154.7)
  arc A2 (118.6, 154.7) -> (117, 153.1) centre (118.6, 153.1) ccw
  line L3 (117, 153.1) -> (117, 152.9)
  arc A3 (117, 152.9) -> (118.6, 151.3) centre (118.6, 152.9) ccw
extrude "Carrier lateral adjustment slot (4)" cut sketch "Carrier lateral adjustment slot (3)" along normal blind 2 bodies 5 in component "05 Replaceable MSP3525 display carrier"
ref_plane "WorkPlane7" through (0, 0, 9) normal (0, 0, 1) x (1, 0, 0) in component "05 Replaceable MSP3525 display carrier"
sketch "PCB mounting boss - measure stack" plane through (0, 0, 9) normal (0, 0, 1) x (1, 0, 0) in component "05 Replaceable MSP3525 display carrier"
  circle A0 centre (22.54, 96.25) radius 3.3
extrude "PCB mounting boss - measure stack (1)" add sketch "PCB mounting boss - measure stack" along normal blind 3 bodies 5 in component "05 Replaceable MSP3525 display carrier"
ref_plane "WorkPlane8" through (0, 0, 8) normal (0, 0, 1) x (1, 0, 0) in component "05 Replaceable MSP3525 display carrier"
sketch "M2.5 insert pilot" plane through (0, 0, 8) normal (0, 0, 1) x (1, 0, 0) in component "05 Replaceable MSP3525 display carrier"
  circle A0 centre (22.54, 96.25) radius 1.65
extrude "M2.5 insert pilot (1)" cut sketch "M2.5 insert pilot" along normal blind 4 bodies 5 in component "05 Replaceable MSP3525 display carrier"
ref_plane "WorkPlane9" through (0, 0, 9) normal (0, 0, 1) x (1, 0, 0) in component "05 Replaceable MSP3525 display carrier"
sketch "PCB mounting boss - measure stack (1)" plane through (0, 0, 9) normal (0, 0, 1) x (1, 0, 0) in component "05 Replaceable MSP3525 display carrier"
  circle A0 centre (22.54, 145.75) radius 3.3
extrude "PCB mounting boss - measure stack (2)" add sketch "PCB mounting boss - measure stack (1)" along normal blind 3 bodies 5 in component "05 Replaceable MSP3525 display carrier"
ref_plane "WorkPlane10" through (0, 0, 8) normal (0, 0, 1) x (1, 0, 0) in component "05 Replaceable MSP3525 display carrier"
sketch "M2.5 insert pilot (1)" plane through (0, 0, 8) normal (0, 0, 1) x (1, 0, 0) in component "05 Replaceable MSP3525 display carrier"
  circle A0 centre (22.54, 145.75) radius 1.65
extrude "M2.5 insert pilot (2)" cut sketch "M2.5 insert pilot (1)" along normal blind 4 bodies 5 in component "05 Replaceable MSP3525 display carrier"
ref_plane "WorkPlane11" through (0, 0, 9) normal (0, 0, 1) x (1, 0, 0) in component "05 Replaceable MSP3525 display carrier"
sketch "PCB mounting boss - measure stack (2)" plane through (0, 0, 9) normal (0, 0, 1) x (1, 0, 0) in component "05 Replaceable MSP3525 display carrier"
  circle A0 centre (114.54, 96.25) radius 3.3
extrude "PCB mounting boss - measure stack (3)" add sketch "PCB mounting boss - measure stack (2)" along normal blind 3 bodies 5 in component "05 Replaceable MSP3525 display carrier"
ref_plane "WorkPlane12" through (0, 0, 8) normal (0, 0, 1) x (1, 0, 0) in component "05 Replaceable MSP3525 display carrier"
sketch "M2.5 insert pilot (2)" plane through (0, 0, 8) normal (0, 0, 1) x (1, 0, 0) in component "05 Replaceable MSP3525 display carrier"
  circle A0 centre (114.54, 96.25) radius 1.65
extrude "M2.5 insert pilot (3)" cut sketch "M2.5 insert pilot (2)" along normal blind 4 bodies 5 in component "05 Replaceable MSP3525 display carrier"
ref_plane "WorkPlane13" through (0, 0, 9) normal (0, 0, 1) x (1, 0, 0) in component "05 Replaceable MSP3525 display carrier"
sketch "PCB mounting boss - measure stack (3)" plane through (0, 0, 9) normal (0, 0, 1) x (1, 0, 0) in component "05 Replaceable MSP3525 display carrier"
  circle A0 centre (114.54, 145.75) radius 3.3
extrude "PCB mounting boss - measure stack (4)" add sketch "PCB mounting boss - measure stack (3)" along normal blind 3 bodies 5 in component "05 Replaceable MSP3525 display carrier"
ref_plane "WorkPlane14" through (0, 0, 8) normal (0, 0, 1) x (1, 0, 0) in component "05 Replaceable MSP3525 display carrier"
sketch "M2.5 insert pilot (3)" plane through (0, 0, 8) normal (0, 0, 1) x (1, 0, 0) in component "05 Replaceable MSP3525 display carrier"
  circle A0 centre (114.54, 145.75) radius 1.65
extrude "M2.5 insert pilot (4)" cut sketch "M2.5 insert pilot (3)" along normal blind 4 bodies 5 in component "05 Replaceable MSP3525 display carrier"
ref_plane "WorkPlane1" through (0, 0, 55) normal (0, 0, 1) x (1, 0, 0) in component "06 ESP32 USB tray"
sketch "Removable controller tray" plane through (0, 0, 55) normal (0, 0, 1) x (1, 0, 0) in component "06 ESP32 USB tray"
  line L0 (15.5, 10) -> (119.5, 10)
  arc A0 (119.5, 10) -> (122.5, 13) centre (119.5, 13) ccw
  line L1 (122.5, 13) -> (122.5, 77)
  arc A1 (122.5, 77) -> (119.5, 80) centre (119.5, 77) ccw
  line L2 (119.5, 80) -> (15.5, 80)
  arc A2 (15.5, 80) -> (12.5, 77) centre (15.5, 77) ccw
  line L3 (12.5, 77) -> (12.5, 13)
  arc A3 (12.5, 13) -> (15.5, 10) centre (15.5, 13) ccw
extrude "Removable controller tray (1)" add sketch "Removable controller tray" along normal blind 3 separate body makes body 6 in component "06 ESP32 USB tray"
ref_plane "WorkPlane2" through (0, 0, 55) normal (0, 0, 1) x (1, 0, 0) in component "06 ESP32 USB tray"
sketch "M3 tray screw" plane through (0, 0, 55) normal (0, 0, 1) x (1, 0, 0) in component "06 ESP32 USB tray"
  circle A0 centre (17.5, 20) radius 1.7
extrude "M3 tray screw (1)" cut sketch "M3 tray screw" along normal blind 3 bodies 6 in component "06 ESP32 USB tray"
ref_plane "WorkPlane19" through (0, 0, 48) normal (0, 0, 1) x (1, 0, 0) in component "02 Ivory shell"
sketch "Tray ledge" plane through (0, 0, 48) normal (0, 0, 1) x (1, 0, 0) in component "02 Ivory shell"
  line L0 (1, 14) -> (24, 14)
  line L1 (24, 14) -> (24, 26)
  line L2 (24, 26) -> (1, 26)
  line L3 (1, 26) -> (1, 14)
extrude "Tray ledge (1)" add sketch "Tray ledge" along normal blind 7 bodies 2 in component "02 Ivory shell"
ref_plane "WorkPlane20" through (0, 0, 50) normal (0, 0, 1) x (1, 0, 0) in component "02 Ivory shell"
sketch "M3 insert pilot (4)" plane through (0, 0, 50) normal (0, 0, 1) x (1, 0, 0) in component "02 Ivory shell"
  circle A0 centre (17.5, 20) radius 2.2
extrude "M3 insert pilot (1)'" cut sketch "M3 insert pilot (4)" along normal blind 5 bodies 2 in component "02 Ivory shell"
ref_plane "WorkPlane3" through (0, 0, 55) normal (0, 0, 1) x (1, 0, 0) in component "06 ESP32 USB tray"
sketch "M3 tray screw (1)" plane through (0, 0, 55) normal (0, 0, 1) x (1, 0, 0) in component "06 ESP32 USB tray"
  circle A0 centre (17.5, 70) radius 1.7
extrude "M3 tray screw (2)" cut sketch "M3 tray screw (1)" along normal blind 3 bodies 6 in component "06 ESP32 USB tray"
ref_plane "WorkPlane21" through (0, 0, 48) normal (0, 0, 1) x (1, 0, 0) in component "02 Ivory shell"
sketch "Tray ledge (1)" plane through (0, 0, 48) normal (0, 0, 1) x (1, 0, 0) in component "02 Ivory shell"
  line L0 (1, 64) -> (24, 64)
  line L1 (24, 64) -> (24, 76)
  line L2 (24, 76) -> (1, 76)
  line L3 (1, 76) -> (1, 64)
extrude "Tray ledge (2)" add sketch "Tray ledge (1)" along normal blind 7 bodies 2 in component "02 Ivory shell"
ref_plane "WorkPlane22" through (0, 0, 50) normal (0, 0, 1) x (1, 0, 0) in component "02 Ivory shell"
sketch "M3 insert pilot (1) (2)" plane through (0, 0, 50) normal (0, 0, 1) x (1, 0, 0) in component "02 Ivory shell"
  circle A0 centre (17.5, 70) radius 2.2
extrude "M3 insert pilot (2)'" cut sketch "M3 insert pilot (1) (2)" along normal blind 5 bodies 2 in component "02 Ivory shell"
ref_plane "WorkPlane4" through (0, 0, 55) normal (0, 0, 1) x (1, 0, 0) in component "06 ESP32 USB tray"
sketch "M3 tray screw (2)" plane through (0, 0, 55) normal (0, 0, 1) x (1, 0, 0) in component "06 ESP32 USB tray"
  circle A0 centre (117.5, 20) radius 1.7
extrude "M3 tray screw (3)" cut sketch "M3 tray screw (2)" along normal blind 3 bodies 6 in component "06 ESP32 USB tray"
ref_plane "WorkPlane23" through (0, 0, 48) normal (0, 0, 1) x (1, 0, 0) in component "02 Ivory shell"
sketch "Tray ledge (2)" plane through (0, 0, 48) normal (0, 0, 1) x (1, 0, 0) in component "02 Ivory shell"
  line L0 (111, 14) -> (134, 14)
  line L1 (134, 14) -> (134, 26)
  line L2 (134, 26) -> (111, 26)
  line L3 (111, 26) -> (111, 14)
extrude "Tray ledge (3)" add sketch "Tray ledge (2)" along normal blind 7 bodies 2 in component "02 Ivory shell"
ref_plane "WorkPlane24" through (0, 0, 50) normal (0, 0, 1) x (1, 0, 0) in component "02 Ivory shell"
sketch "M3 insert pilot (2) (2)" plane through (0, 0, 50) normal (0, 0, 1) x (1, 0, 0) in component "02 Ivory shell"
  circle A0 centre (117.5, 20) radius 2.2
extrude "M3 insert pilot (3)'" cut sketch "M3 insert pilot (2) (2)" along normal blind 5 bodies 2 in component "02 Ivory shell"
ref_plane "WorkPlane5" through (0, 0, 55) normal (0, 0, 1) x (1, 0, 0) in component "06 ESP32 USB tray"
sketch "M3 tray screw (3)" plane through (0, 0, 55) normal (0, 0, 1) x (1, 0, 0) in component "06 ESP32 USB tray"
  circle A0 centre (117.5, 70) radius 1.7
extrude "M3 tray screw (4)" cut sketch "M3 tray screw (3)" along normal blind 3 bodies 6 in component "06 ESP32 USB tray"
ref_plane "WorkPlane25" through (0, 0, 48) normal (0, 0, 1) x (1, 0, 0) in component "02 Ivory shell"
sketch "Tray ledge (3)" plane through (0, 0, 48) normal (0, 0, 1) x (1, 0, 0) in component "02 Ivory shell"
  line L0 (111, 64) -> (134, 64)
  line L1 (134, 64) -> (134, 76)
  line L2 (134, 76) -> (111, 76)
  line L3 (111, 76) -> (111, 64)
extrude "Tray ledge (4)" add sketch "Tray ledge (3)" along normal blind 7 bodies 2 in component "02 Ivory shell"
ref_plane "WorkPlane26" through (0, 0, 50) normal (0, 0, 1) x (1, 0, 0) in component "02 Ivory shell"
sketch "M3 insert pilot (3) (2)" plane through (0, 0, 50) normal (0, 0, 1) x (1, 0, 0) in component "02 Ivory shell"
  circle A0 centre (117.5, 70) radius 2.2
extrude "M3 insert pilot (4)'" cut sketch "M3 insert pilot (3) (2)" along normal blind 5 bodies 2 in component "02 Ivory shell"
ref_plane "WorkPlane6" through (0, 0, 55) normal (0, 0, 1) x (1, 0, 0) in component "06 ESP32 USB tray"
sketch "Antenna keepout" plane through (0, 0, 55) normal (0, 0, 1) x (1, 0, 0) in component "06 ESP32 USB tray"
  line L0 (89, 17) -> (105, 17)
  arc A0 (105, 17) -> (106, 18) centre (105, 18) ccw
  line L1 (106, 18) -> (106, 48)
  arc A1 (106, 48) -> (105, 49) centre (105, 48) ccw
  line L2 (105, 49) -> (89, 49)
  arc A2 (89, 49) -> (88, 48) centre (89, 48) ccw
  line L3 (88, 48) -> (88, 18)
  arc A3 (88, 18) -> (89, 17) centre (89, 18) ccw
extrude "Antenna keepout (1)" cut sketch "Antenna keepout" along normal blind 3 bodies 6 in component "06 ESP32 USB tray"
ref_plane "WorkPlane7" through (0, 0, 55) normal (0, 0, 1) x (1, 0, 0) in component "06 ESP32 USB tray"
sketch "Controller tie slot" plane through (0, 0, 55) normal (0, 0, 1) x (1, 0, 0) in component "06 ESP32 USB tray"
  line L0 (46.5, 16) -> (49.5, 16)
  arc A0 (49.5, 16) -> (50, 16.5) centre (49.5, 16.5) ccw
  line L1 (50, 16.5) -> (50, 17.5)
  arc A1 (50, 17.5) -> (49.5, 18) centre (49.5, 17.5) ccw
  line L2 (49.5, 18) -> (46.5, 18)
  arc A2 (46.5, 18) -> (46, 17.5) centre (46.5, 17.5) ccw
  line L3 (46, 17.5) -> (46, 16.5)
  arc A3 (46, 16.5) -> (46.5, 16) centre (46.5, 16.5) ccw
extrude "Controller tie slot (1)" cut sketch "Controller tie slot" along normal blind 3 bodies 6 in component "06 ESP32 USB tray"
ref_plane "WorkPlane8" through (0, 0, 55) normal (0, 0, 1) x (1, 0, 0) in component "06 ESP32 USB tray"
sketch "Controller tie slot (1)" plane through (0, 0, 55) normal (0, 0, 1) x (1, 0, 0) in component "06 ESP32 USB tray"
  line L0 (46.5, 47) -> (49.5, 47)
  arc A0 (49.5, 47) -> (50, 47.5) centre (49.5, 47.5) ccw
  line L1 (50, 47.5) -> (50, 48.5)
  arc A1 (50, 48.5) -> (49.5, 49) centre (49.5, 48.5) ccw
  line L2 (49.5, 49) -> (46.5, 49)
  arc A2 (46.5, 49) -> (46, 48.5) centre (46.5, 48.5) ccw
  line L3 (46, 48.5) -> (46, 47.5)
  arc A3 (46, 47.5) -> (46.5, 47) centre (46.5, 47.5) ccw
extrude "Controller tie slot (2)" cut sketch "Controller tie slot (1)" along normal blind 3 bodies 6 in component "06 ESP32 USB tray"
ref_plane "WorkPlane9" through (0, 0, 58) normal (0, 0, 1) x (1, 0, 0) in component "06 ESP32 USB tray"
sketch "PCB support - verify underside clearance" plane through (0, 0, 58) normal (0, 0, 1) x (1, 0, 0) in component "06 ESP32 USB tray"
  line L0 (46, 27) -> (50, 27)
  line L1 (50, 27) -> (50, 31)
  line L2 (50, 31) -> (46, 31)
  line L3 (46, 31) -> (46, 27)
extrude "PCB support - verify underside clearance (1)" add sketch "PCB support - verify underside clearance" along normal blind 5 bodies 6 in component "06 ESP32 USB tray"
ref_plane "WorkPlane10" through (0, 0, 58) normal (0, 0, 1) x (1, 0, 0) in component "06 ESP32 USB tray"
sketch "PCB support - verify underside clearance (1)" plane through (0, 0, 58) normal (0, 0, 1) x (1, 0, 0) in component "06 ESP32 USB tray"
  line L0 (46, 36) -> (50, 36)
  line L1 (50, 36) -> (50, 40)
  line L2 (50, 40) -> (46, 40)
  line L3 (46, 40) -> (46, 36)
extrude "PCB support - verify underside clearance (2)" add sketch "PCB support - verify underside clearance (1)" along normal blind 5 bodies 6 in component "06 ESP32 USB tray"
ref_plane "WorkPlane11" through (0, 0, 55) normal (0, 0, 1) x (1, 0, 0) in component "06 ESP32 USB tray"
sketch "Controller tie slot (2)" plane through (0, 0, 55) normal (0, 0, 1) x (1, 0, 0) in component "06 ESP32 USB tray"
  line L0 (78.5, 16) -> (81.5, 16)
  arc A0 (81.5, 16) -> (82, 16.5) centre (81.5, 16.5) ccw
  line L1 (82, 16.5) -> (82, 17.5)
  arc A1 (82, 17.5) -> (81.5, 18) centre (81.5, 17.5) ccw
  line L2 (81.5, 18) -> (78.5, 18)
  arc A2 (78.5, 18) -> (78, 17.5) centre (78.5, 17.5) ccw
  line L3 (78, 17.5) -> (78, 16.5)
  arc A3 (78, 16.5) -> (78.5, 16) centre (78.5, 16.5) ccw
extrude "Controller tie slot (3)" cut sketch "Controller tie slot (2)" along normal blind 3 bodies 6 in component "06 ESP32 USB tray"
ref_plane "WorkPlane12" through (0, 0, 55) normal (0, 0, 1) x (1, 0, 0) in component "06 ESP32 USB tray"
sketch "Controller tie slot (3)" plane through (0, 0, 55) normal (0, 0, 1) x (1, 0, 0) in component "06 ESP32 USB tray"
  line L0 (78.5, 47) -> (81.5, 47)
  arc A0 (81.5, 47) -> (82, 47.5) centre (81.5, 47.5) ccw
  line L1 (82, 47.5) -> (82, 48.5)
  arc A1 (82, 48.5) -> (81.5, 49) centre (81.5, 48.5) ccw
  line L2 (81.5, 49) -> (78.5, 49)
  arc A2 (78.5, 49) -> (78, 48.5) centre (78.5, 48.5) ccw
  line L3 (78, 48.5) -> (78, 47.5)
  arc A3 (78, 47.5) -> (78.5, 47) centre (78.5, 47.5) ccw
extrude "Controller tie slot (4)" cut sketch "Controller tie slot (3)" along normal blind 3 bodies 6 in component "06 ESP32 USB tray"
ref_plane "WorkPlane13" through (0, 0, 58) normal (0, 0, 1) x (1, 0, 0) in component "06 ESP32 USB tray"
sketch "PCB support - verify underside clearance (2)" plane through (0, 0, 58) normal (0, 0, 1) x (1, 0, 0) in component "06 ESP32 USB tray"
  line L0 (78, 27) -> (82, 27)
  line L1 (82, 27) -> (82, 31)
  line L2 (82, 31) -> (78, 31)
  line L3 (78, 31) -> (78, 27)
extrude "PCB support - verify underside clearance (3)" add sketch "PCB support - verify underside clearance (2)" along normal blind 5 bodies 6 in component "06 ESP32 USB tray"
ref_plane "WorkPlane14" through (0, 0, 58) normal (0, 0, 1) x (1, 0, 0) in component "06 ESP32 USB tray"
sketch "PCB support - verify underside clearance (3)" plane through (0, 0, 58) normal (0, 0, 1) x (1, 0, 0) in component "06 ESP32 USB tray"
  line L0 (78, 36) -> (82, 36)
  line L1 (82, 36) -> (82, 40)
  line L2 (82, 40) -> (78, 40)
  line L3 (78, 40) -> (78, 36)